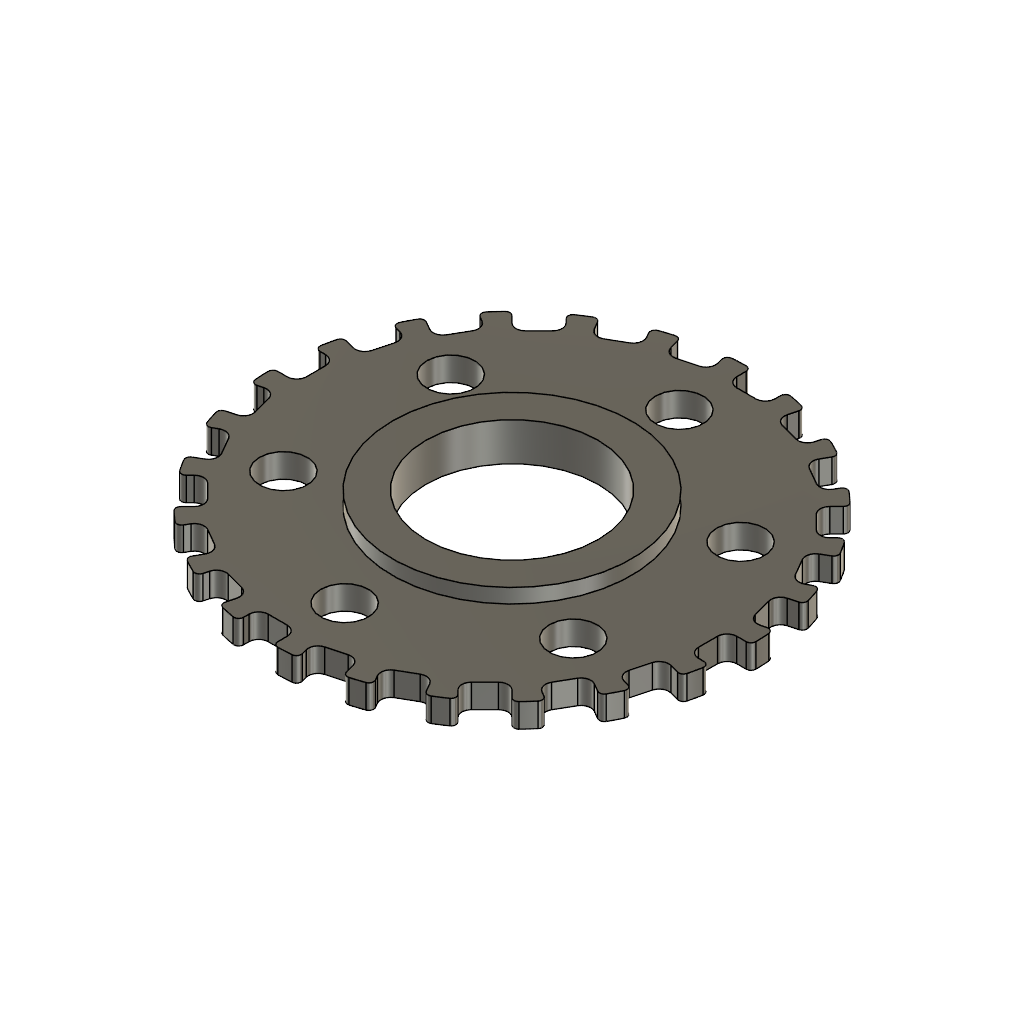
pignon (Autodesk Fusion 360 design; units mm, degrees)
part number: 2026-10-23-08-20-56-668
Autodesk Fusion 360 part; units mm, degrees
sketch "Esquisse1" plane through (0, 0, 0) normal (0, 0, 1) x (1, 0, 0)
  circle A0 centre (0, 0) radius 50
  circle A1 centre (0, 0) radius 25
  circle A2 centre (0, 0) radius 18
  line L0 (-70, 35) -> (70, 35) construction
  circle A3 centre (0, 35) radius 5
  circle A4 centre (-30.3109, 17.5) radius 5
  circle A5 centre (-30.3109, -17.5) radius 5
  circle A6 centre (0, -35) radius 5
  circle A7 centre (30.3109, -17.5) radius 5
  circle A8 centre (30.3109, 17.5) radius 5
  dimension "d1" = 100
  dimension "d2" = 50
  dimension "d3" = 36
  dimension "d4" = 35
  dimension "d5" = 10
  dimension "d7" = 360
  constraint coincident A0.centre A1.centre
  constraint horizontal L0
  constraint midpoint L0 A3.centre
  measures "d1" diameter of A0
  measures "d2" diameter of A1
  measures "d3" diameter of A2
  measures "d4" distance of A0.centre L0
  measures "d5" diameter of A3
extrude "Extrusion1" add sketch "Esquisse1" along normal blind 5 contours A0 | A1
sketch "Esquisse2" plane through (0, 0, 5) normal (0, 0, 1) x (-1, 0, 0)
  circle A0 centre (-30.3109, 17.5) radius 5
  circle A1 centre (30.3109, -17.5) radius 5
  circle A2 centre (0, -35) radius 5
  circle A3 centre (-30.3109, -17.5) radius 5
  circle A4 centre (0, 35) radius 5
  circle A5 centre (30.3109, 17.5) radius 5
  circle A6 centre (0, 0) radius 18
  circle A7 centre (0, 0) radius 50
  line L0 (0, -50) -> (0, -45)
  line L1 (0, -45) -> (-8, -45)
  line L2 (-8, -45) -> (-8, -50)
  line L3 (-8, -50) -> (0, -50)
  constraint coincident A7 L0.start
  constraint perpendicular L0 L1
  constraint perpendicular L1 L2
  constraint perpendicular L0 L3
extrude "Extrusion2" cut sketch "Esquisse2" along normal mid plane 14 contours A7 L0 L1 L2 picked at (-4.4487, -46.5711)
fillet "Congé1" radius 1 2 edges at (8, 49.3559, 2.5) (0, 50, 2.5)
fillet "Congé2" radius 2 2 edges at (0, 45, 2.5) (8, 45, 2.5)
pattern_circular "Réseau C1" count 24 over 360 about axis through (0, 0, 0) along (0, 0, 1) of 7 faces at (-0.0564, 49.321, 1.6667) (0, 48.3265, 1.6667) (0.0091, 46.8099, 1.6667) (3.3333, 45, 1.6667) (6.0952, 45.0023, 3.3333) (8, 47.3888, 1.6667) (9.0871, 49.1626, 1.6667)
extrude "Extrusion3" add sketch "Esquisse1" along normal blind 3 contours A1
extrude "Extrusion4" add sketch "Esquisse1" along normal blind 8 contours A1
